Y-Arm native (Autodesk Fusion 360 design; units mm, degrees)
part number: 2026-10-13-21-21-54-886
Autodesk Fusion 360 part; units mm, degrees
ref_plane "WorkPlane1" through (1.5, 0, 0) normal (1, 0, 0) x (0, 1, 0)
sketch "Profile" plane through (1.5, 0, 0) normal (1, 0, 0) x (0, 0, -1)
  line L0 (-25.2691, 28.7293) -> (-36.8746, 12.1549)
  arc A0 (-36.8746, 12.1549) -> (-31.2507, 8.2171) centre (-34.0626, 10.186) ccw
  line L1 (-31.2507, 8.2171) -> (-23.165, 19.7647)
  arc A1 (-17.0125, 20.9474) -> (-23.165, 19.7647) centre (-19.4789, 17.1838) ccw
  arc A2 (-17.0125, 20.9474) -> (-14.0887, 21.055) centre (-15.6265, 23.0624) ccw
  arc A3 (-11.0623, 21.1198) -> (-14.0887, 21.055) centre (-12.5313, 19.0219) ccw
  line L2 (-11.0623, 21.1198) -> (-0.9966, 14.0718)
  arc A4 (-0.0222, 11.2054) -> (-0.9966, 14.0718) centre (-2.4658, 11.9735) ccw
  arc A5 (-0.0222, 11.2054) -> (0.9398, 8.3758) centre (2.3902, 10.4472) ccw
  line L3 (0.9398, 8.3758) -> (4.2445, 6.0618)
  arc A6 (4.2445, 6.0618) -> (7.7661, 11.0912) centre (6.0053, 8.5765) ccw
  line L4 (7.7661, 11.0912) -> (2.8028, 14.5666)
  arc A7 (2.5486, 16.7827) -> (2.8028, 14.5666) centre (4.7146, 15.9085) ccw
  arc A8 (2.5486, 16.7827) -> (1.9885, 18.6724) centre (1.0802, 17.3753) ccw
  line L5 (1.9885, 18.6724) -> (-7.7597, 25.4983)
  arc A9 (-7.7597, 25.4983) -> (-9.7271, 25.3783) centre (-8.668, 24.2012) ccw
  arc A10 (-11.8967, 24.8593) -> (-9.7271, 25.3783) centre (-11.2893, 27.1147) ccw
  line L6 (-11.8967, 24.8593) -> (-19.0018, 29.8344)
  arc A11 (-19.0018, 29.8344) -> (-25.2691, 28.7293) centre (-21.5829, 26.1482) ccw
  dimension "d13" = 3.4327
  dimension "d14" = 4.4998
  dimension "d15" = 2.5287
  dimension "d16" = 2.5611
  dimension "d17" = 2.5615
  dimension "d18" = 3.0699
  dimension "d19" = 2.3357
  dimension "d20" = 1.5835
  dimension "d21" = 4.5
  dimension "d22" = 34.0626
  dimension "d23" = 10.186
  dimension "d24" = 19.4789
  dimension "d25" = 17.1838
  dimension "d26" = 15.6265
  dimension "d27" = 12.5313
  dimension "d28" = 2.4658
  dimension "d29" = 11.9735
  dimension "d30" = 2.3902
  dimension "d31" = 6.0053
  dimension "d32" = 8.5765
  dimension "d33" = 4.7146
  dimension "d34" = 15.9085
  dimension "d35" = 1.0802
  dimension "d36" = 8.668
  dimension "d37" = 24.2012
  dimension "d38" = 11.2893
  dimension "d39" = 21.5829
  dimension "d40" = 26.1482
  dimension "d41" = 7.7661
  dimension "d42" = 11.8967
  constraint tangent L0 A11
  constraint tangent L0 A0
  constraint tangent A0 L1
  constraint tangent L1 A1
  constraint tangent A1 A2
  constraint tangent A2 A3
  constraint tangent A3 L2
  constraint tangent L2 A4
  constraint tangent A4 A5
  constraint tangent A5 L3
  constraint tangent L3 A6
  constraint tangent A6 L4
  constraint tangent A7 A8
  constraint tangent A8 L5
  constraint tangent L5 A9
  constraint tangent A9 A10
  constraint tangent L6 A11
  constraint equal A2 A5
  constraint equal A8 A9
  constraint equal A7 A10
  measures "d13" radius of A0
  measures "d14" radius of A1
  measures "d15" radius of A2
  measures "d16" radius of A3
  measures "d17" radius of A4
  measures "d18" radius of A6
  measures "d19" radius of A7
  measures "d20" radius of A8
  measures "d21" radius of A11
  measures "d22" horizontal distance of origin A0.centre
  measures "d23" vertical distance of origin A0.centre
  measures "d24" horizontal distance of origin A1.centre
  measures "d25" vertical distance of origin A1.centre
  measures "d26" horizontal distance of origin A2.centre
  measures "d27" horizontal distance of origin A3.centre
  measures "d28" horizontal distance of origin A4.centre
  measures "d29" vertical distance of origin A4.centre
  measures "d30" horizontal distance of origin A5.centre
  measures "d31" horizontal distance of origin A6.centre
  measures "d32" vertical distance of origin A6.centre
  measures "d33" horizontal distance of origin A7.centre
  measures "d34" vertical distance of origin A7.centre
  measures "d35" horizontal distance of origin A8.centre
  measures "d36" horizontal distance of origin A9.centre
  measures "d37" vertical distance of origin A9.centre
  measures "d38" horizontal distance of origin A10.centre
  measures "d39" horizontal distance of origin A11.centre
  measures "d40" vertical distance of origin A11.centre
  measures "d41" horizontal distance of origin A6.end
  measures "d42" horizontal distance of origin A10.start
extrude "Profile (1)" add sketch "Profile" along normal mid plane 3
ref_plane "WorkPlane2" through (1.5, 0, 0) normal (1, 0, 0) x (0, 1, 0)
sketch "Hole 1" plane through (1.5, 0, 0) normal (1, 0, 0) x (0, 0, -1)
  circle A0 centre (6.0053, 8.5765) radius 1.75
  dimension "d43" = 3.5
  dimension "d44" = 6.0053
  dimension "d45" = 8.5765
  measures "d43" diameter of A0
  measures "d44" horizontal distance of origin A0.centre
  measures "d45" vertical distance of origin A0.centre
extrude "Hole 1 (1)" cut sketch "Hole 1" along normal mid plane 3
ref_plane "WorkPlane3" through (1.5, 0, 0) normal (1, 0, 0) x (0, 1, 0)
sketch "Hole 2" plane through (1.5, 0, 0) normal (1, 0, 0) x (0, 0, -1)
  circle A0 centre (-34.0626, 10.186) radius 1.25
  dimension "d46" = 2.5001
  dimension "d47" = 34.0626
  dimension "d48" = 10.186
  measures "d46" diameter of A0
  measures "d47" horizontal distance of origin A0.centre
  measures "d48" vertical distance of origin A0.centre
extrude "Hole 2 (1)" cut sketch "Hole 2" along normal mid plane 3
named bodies: "Y-Arm native"
